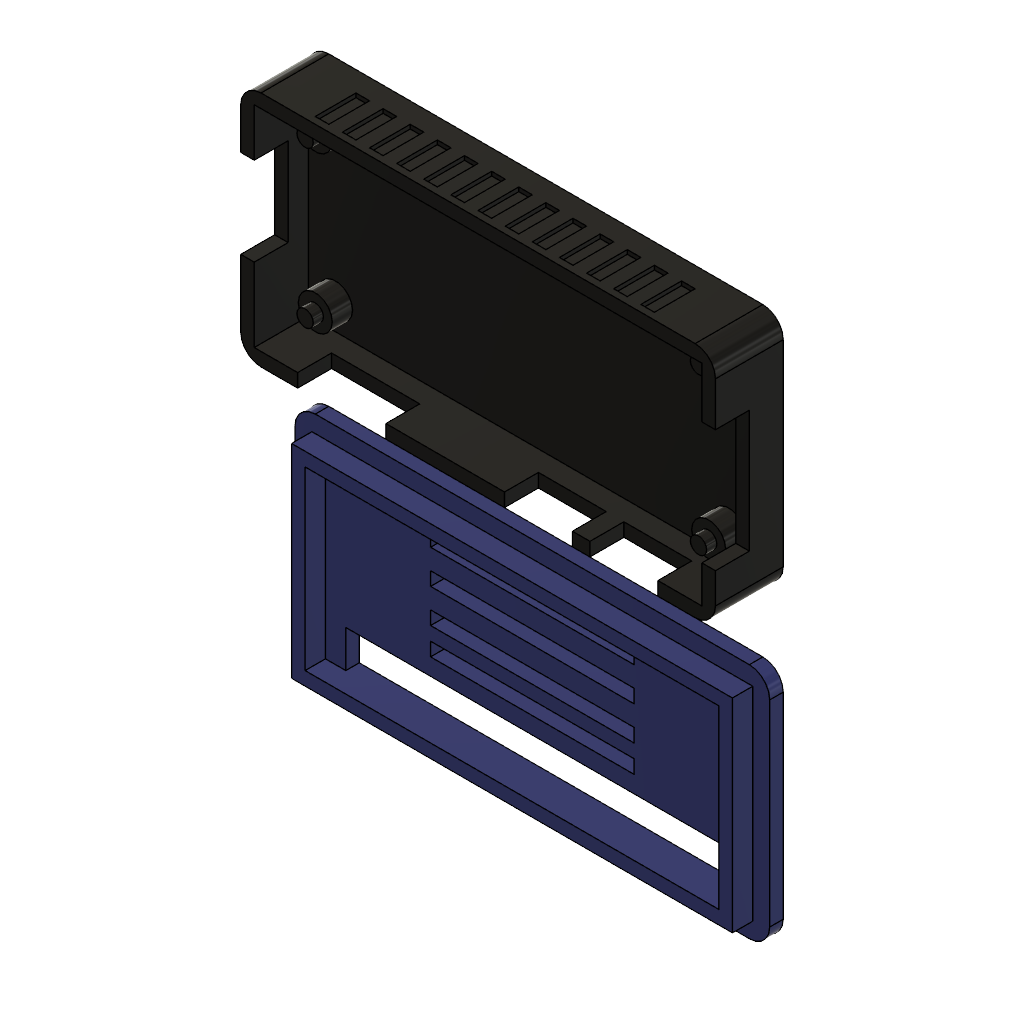
raspberry full assembly (Autodesk Fusion 360 archive; units mm, degrees)
design "raspberry"
part number: 2026-11-03-22-19-11-601
Autodesk Fusion 360 part; units mm, degrees
sketch "Sketch1" plane through (0, 0, 0) normal (0, 0, 1) x (1, 0, 0)
  line L0 (-35, -17.5) -> (35, -17.5)
  line L1 (35, -17.5) -> (35, 17.5)
  line L2 (35, 17.5) -> (-35, 17.5)
  line L3 (-35, 17.5) -> (-35, -17.5)
extrude "Extrude1" add sketch "Sketch1" along normal blind 10 makes body 1
ref_plane "WorkPlane1" through (0, 0, 2) normal (0, 0, 1) x (1, 0, 0)
sketch "Sketch2" plane through (0, 0, 2) normal (0, 0, 1) x (1, 0, 0)
  line L0 (-33, -15.5) -> (33, -15.5)
  line L1 (33, -15.5) -> (33, 15.5)
  line L2 (33, 15.5) -> (-33, 15.5)
  line L3 (-33, 15.5) -> (-33, -15.5)
extrude "Extrude2" cut sketch "Sketch2" along normal blind 8 bodies 1
sketch "Sketch3" plane through (0, 0, 2) normal (0, 0, 1) x (1, 0, 0)
  circle A0 centre (-29, -11.5) radius 2.5
  circle A1 centre (29, -11.5) radius 2.5
  circle A2 centre (-29, 11.5) radius 2.5
  circle A3 centre (29, 11.5) radius 2.5
extrude "Extrude3" add sketch "Sketch3" along normal blind 3 bodies 1
ref_plane "WorkPlane2" through (0, 0, 5) normal (0, 0, 1) x (1, 0, 0)
sketch "Sketch4" plane through (0, 0, 5) normal (0, 0, 1) x (1, 0, 0)
  circle A0 centre (-29, -11.5) radius 1.2
  circle A1 centre (29, -11.5) radius 1.2
  circle A2 centre (-29, 11.5) radius 1.2
  circle A3 centre (29, 11.5) radius 1.2
extrude "Extrude4" add sketch "Sketch4" along normal blind 1.5 bodies 1
ref_plane "WorkPlane3" through (0, 0, 10) normal (0, 0, 1) x (1, 0, 0)
sketch "Sketch5" plane through (0, 0, 10) normal (0, 0, 1) x (1, 0, 0)
  line L0 (-35, -17.5) -> (35, -17.5)
  line L1 (35, -17.5) -> (35, 17.5)
  line L2 (35, 17.5) -> (-35, 17.5)
  line L3 (-35, 17.5) -> (-35, -17.5)
extrude "Extrude5" add sketch "Sketch5" along normal blind 2 separate body makes body 2
sketch "Sketch6" plane through (0, 0, 10) normal (0, 0, 1) x (1, 0, 0)
  line L0 (-32.5, -15) -> (32.5, -15)
  line L1 (32.5, -15) -> (32.5, 15)
  line L2 (32.5, 15) -> (-32.5, 15)
  line L3 (-32.5, 15) -> (-32.5, -15)
extrude "Extrude6" add sketch "Sketch6" against normal blind 3 bodies 2
ref_plane "WorkPlane4" through (0, 0, 5) normal (0, 0, 1) x (1, 0, 0)
sketch "Sketch7" plane through (0, 0, 5) normal (0, 0, 1) x (1, 0, 0)
  line L0 (-26.6, -18) -> (-13.6, -18)
  line L1 (-13.6, -18) -> (-13.6, -15)
  line L2 (-13.6, -15) -> (-26.6, -15)
  line L3 (-26.6, -15) -> (-26.6, -18)
  line L4 (3.9, -18) -> (13.9, -18)
  line L5 (13.9, -18) -> (13.9, -15)
  line L6 (13.9, -15) -> (3.9, -15)
  line L7 (3.9, -15) -> (3.9, -18)
  line L8 (16.5, -18) -> (26.5, -18)
  line L9 (26.5, -18) -> (26.5, -15)
  line L10 (26.5, -15) -> (16.5, -15)
  line L11 (16.5, -15) -> (16.5, -18)
  line L12 (-35.5, -4.6) -> (-32, -4.6)
  line L13 (-32, -4.6) -> (-32, 8.4)
  line L14 (-32, 8.4) -> (-35.5, 8.4)
  line L15 (-35.5, 8.4) -> (-35.5, -4.6)
  line L16 (32, -10) -> (35.5, -10)
  line L17 (35.5, -10) -> (35.5, 8)
  line L18 (35.5, 8) -> (32, 8)
  line L19 (32, 8) -> (32, -10)
extrude "Extrude7" cut sketch "Sketch7" along normal blind 4.5 bodies 1
ref_plane "WorkPlane5" through (0, 0, 10) normal (0, 0, 1) x (1, 0, 0)
sketch "Sketch8" plane through (0, 0, 10) normal (0, 0, 1) x (1, 0, 0)
  line L0 (-30.5, -13) -> (30.5, -13)
  line L1 (30.5, -13) -> (30.5, 13)
  line L2 (30.5, 13) -> (-30.5, 13)
  line L3 (-30.5, 13) -> (-30.5, -13)
extrude "Extrude8" cut sketch "Sketch8" against normal blind 3 bodies 2
sketch "Sketch9" plane through (0, 0, 10) normal (0, 0, 1) x (1, 0, 0)
  line L0 (-15, -11) -> (15, -11)
  line L1 (15, -11) -> (15, -9)
  line L2 (15, -9) -> (-15, -9)
  line L3 (-15, -9) -> (-15, -11)
  line L4 (-15, -6) -> (15, -6)
  line L5 (15, -6) -> (15, -4)
  line L6 (15, -4) -> (-15, -4)
  line L7 (-15, -4) -> (-15, -6)
  line L8 (-15, -1) -> (15, -1)
  line L9 (15, -1) -> (15, 1)
  line L10 (15, 1) -> (-15, 1)
  line L11 (-15, 1) -> (-15, -1)
  line L12 (-15, 3) -> (15, 3)
  line L13 (15, 3) -> (15, 5)
  line L14 (15, 5) -> (-15, 5)
  line L15 (-15, 5) -> (-15, 3)
  line L16 (-27.5, 7.5) -> (27.5, 7.5)
  line L17 (27.5, 7.5) -> (27.5, 13)
  line L18 (27.5, 13) -> (-27.5, 13)
  line L19 (-27.5, 13) -> (-27.5, 7.5)
extrude "Extrude9" cut sketch "Sketch9" along normal blind 2 bodies 2
fillet "Fillet1" radius 3 4 edges at (-35, 17.5, 5) (35, 17.5, 5) (35, -17.5, 5) (-35, -17.5, 5) on bodies 1
fillet "Fillet2" radius 3 4 edges at (-35, 17.5, 11) (35, 17.5, 11) (35, -17.5, 11) (-35, -17.5, 11) on bodies 2
move_body "Move1" bodies 2 to x (1, 0, 0) y (0, -1, 0) z (0, 0, -1) at (0, -45, 12)
ref_plane "WorkPlane6" through (0, 0, 9) normal (0, 0, 1) x (1, 0, 0)
sketch "Sketch10" plane through (0, 0, 9) normal (0, 0, 1) x (1, 0, 0)
  line L0 (-26.6, -18) -> (-13.6, -18)
  line L1 (-13.6, -18) -> (-13.6, -15)
  line L2 (-13.6, -15) -> (-26.6, -15)
  line L3 (-26.6, -15) -> (-26.6, -18)
  line L4 (3.9, -18) -> (13.9, -18)
  line L5 (13.9, -18) -> (13.9, -15)
  line L6 (13.9, -15) -> (3.9, -15)
  line L7 (3.9, -15) -> (3.9, -18)
  line L8 (16.5, -18) -> (26.5, -18)
  line L9 (26.5, -18) -> (26.5, -15)
  line L10 (26.5, -15) -> (16.5, -15)
  line L11 (16.5, -15) -> (16.5, -18)
  line L12 (-35.5, -4.6) -> (-32, -4.6)
  line L13 (-32, -4.6) -> (-32, 8.4)
  line L14 (-32, 8.4) -> (-35.5, 8.4)
  line L15 (-35.5, 8.4) -> (-35.5, -4.6)
  line L16 (32, -10) -> (35.5, -10)
  line L17 (35.5, -10) -> (35.5, 8)
  line L18 (35.5, 8) -> (32, 8)
  line L19 (32, 8) -> (32, -10)
extrude "Extrude10" cut sketch "Sketch10" along normal blind 3 bodies 1
ref_plane "WorkPlane7" through (0, 0, 3) normal (0, 0, 1) x (1, 0, 0)
sketch "Sketch11" plane through (0, 0, 3) normal (0, 0, 1) x (1, 0, 0)
  line L0 (-25, 16.9) -> (-23, 16.9)
  line L1 (-23, 16.9) -> (-23, 18)
  line L2 (-23, 18) -> (-25, 18)
  line L3 (-25, 18) -> (-25, 16.9)
  line L4 (-21, 16.9) -> (-19, 16.9)
  line L5 (-19, 16.9) -> (-19, 18)
  line L6 (-19, 18) -> (-21, 18)
  line L7 (-21, 18) -> (-21, 16.9)
  line L8 (-17, 16.9) -> (-15, 16.9)
  line L9 (-15, 16.9) -> (-15, 18)
  line L10 (-15, 18) -> (-17, 18)
  line L11 (-17, 18) -> (-17, 16.9)
  line L12 (-13, 16.9) -> (-11, 16.9)
  line L13 (-11, 16.9) -> (-11, 18)
  line L14 (-11, 18) -> (-13, 18)
  line L15 (-13, 18) -> (-13, 16.9)
  line L16 (-9, 16.9) -> (-7, 16.9)
  line L17 (-7, 16.9) -> (-7, 18)
  line L18 (-7, 18) -> (-9, 18)
  line L19 (-9, 18) -> (-9, 16.9)
  line L20 (-5, 16.9) -> (-3, 16.9)
  line L21 (-3, 16.9) -> (-3, 18)
  line L22 (-3, 18) -> (-5, 18)
  line L23 (-5, 18) -> (-5, 16.9)
  line L24 (-1, 16.9) -> (1, 16.9)
  line L25 (1, 16.9) -> (1, 18)
  line L26 (1, 18) -> (-1, 18)
  line L27 (-1, 18) -> (-1, 16.9)
  line L28 (3, 16.9) -> (5, 16.9)
  line L29 (5, 16.9) -> (5, 18)
  line L30 (5, 18) -> (3, 18)
  line L31 (3, 18) -> (3, 16.9)
  line L32 (7, 16.9) -> (9, 16.9)
  line L33 (9, 16.9) -> (9, 18)
  line L34 (9, 18) -> (7, 18)
  line L35 (7, 18) -> (7, 16.9)
  line L36 (11, 16.9) -> (13, 16.9)
  line L37 (13, 16.9) -> (13, 18)
  line L38 (13, 18) -> (11, 18)
  line L39 (11, 18) -> (11, 16.9)
  line L40 (15, 16.9) -> (17, 16.9)
  line L41 (17, 16.9) -> (17, 18)
  line L42 (17, 18) -> (15, 18)
  line L43 (15, 18) -> (15, 16.9)
  line L44 (19, 16.9) -> (21, 16.9)
  line L45 (21, 16.9) -> (21, 18)
  line L46 (21, 18) -> (19, 18)
  line L47 (19, 18) -> (19, 16.9)
  line L48 (23, 16.9) -> (25, 16.9)
  line L49 (25, 16.9) -> (25, 18)
  line L50 (25, 18) -> (23, 18)
  line L51 (23, 18) -> (23, 16.9)
  line L52 (-31, -18) -> (-29, -18)
  line L53 (-29, -18) -> (-29, -16.9)
  line L54 (-29, -16.9) -> (-31, -16.9)
  line L55 (-31, -16.9) -> (-31, -18)
  line L56 (-10, -18) -> (-8, -18)
  line L57 (-8, -18) -> (-8, -16.9)
  line L58 (-8, -16.9) -> (-10, -16.9)
  line L59 (-10, -16.9) -> (-10, -18)
  line L60 (-6, -18) -> (-4, -18)
  line L61 (-4, -18) -> (-4, -16.9)
  line L62 (-4, -16.9) -> (-6, -16.9)
  line L63 (-6, -16.9) -> (-6, -18)
  line L64 (-2, -18) -> (0, -18)
  line L65 (0, -18) -> (0, -16.9)
  line L66 (0, -16.9) -> (-2, -16.9)
  line L67 (-2, -16.9) -> (-2, -18)
  line L68 (29, -18) -> (31, -18)
  line L69 (31, -18) -> (31, -16.9)
  line L70 (31, -16.9) -> (29, -16.9)
  line L71 (29, -16.9) -> (29, -18)
extrude "Extrude11" cut sketch "Sketch11" along normal blind 6 bodies 1
sketch "Sketch12" plane through (0, 0, 0) normal (0, 0, 1) x (1, 0, 0)
  line L0 (-32.5, -60) -> (32.5, -60)
  line L1 (32.5, -60) -> (32.5, -30)
  line L2 (32.5, -30) -> (-32.5, -30)
  line L3 (-32.5, -30) -> (-32.5, -60)
  line L4 (-31.9, -59.4) -> (31.9, -59.4)
  line L5 (31.9, -59.4) -> (31.9, -30.6)
  line L6 (31.9, -30.6) -> (-31.9, -30.6)
  line L7 (-31.9, -30.6) -> (-31.9, -59.4)
extrude "Extrude12" cut sketch "Sketch12" along normal blind 0.5 bodies 2
sketch "Sketch13" plane through (0, 0, 0) normal (0, 0, 1) x (1, 0, 0)
  circle A0 centre (-18, -49.8) radius 0.9
  circle A1 centre (-18, -47.4) radius 0.9
  circle A2 centre (-18, -45) radius 0.9
  circle A3 centre (-18, -42.6) radius 0.9
  circle A4 centre (-18, -40.2) radius 0.9
  circle A5 centre (-20.5, -49.8) radius 0.75
  circle A6 centre (-20.5, -47.4) radius 0.75
  circle A7 centre (-20.5, -45) radius 0.75
  circle A8 centre (-20.5, -42.6) radius 0.75
  circle A9 centre (-20.5, -40.2) radius 0.75
  circle A10 centre (-23, -49.8) radius 0.6
  circle A11 centre (-23, -47.4) radius 0.6
  circle A12 centre (-23, -45) radius 0.6
  circle A13 centre (-23, -42.6) radius 0.6
  circle A14 centre (-23, -40.2) radius 0.6
  circle A15 centre (-25.5, -49.8) radius 0.45
  circle A16 centre (-25.5, -47.4) radius 0.45
  circle A17 centre (-25.5, -45) radius 0.45
  circle A18 centre (-25.5, -42.6) radius 0.45
  circle A19 centre (-25.5, -40.2) radius 0.45
  circle A20 centre (-28, -49.8) radius 0.3
  circle A21 centre (-28, -47.4) radius 0.3
  circle A22 centre (-28, -45) radius 0.3
  circle A23 centre (-28, -42.6) radius 0.3
  circle A24 centre (-28, -40.2) radius 0.3
  circle A25 centre (18, -49.8) radius 0.9
  circle A26 centre (18, -47.4) radius 0.9
  circle A27 centre (18, -45) radius 0.9
  circle A28 centre (18, -42.6) radius 0.9
  circle A29 centre (18, -40.2) radius 0.9
  circle A30 centre (20.5, -49.8) radius 0.75
  circle A31 centre (20.5, -47.4) radius 0.75
  circle A32 centre (20.5, -45) radius 0.75
  circle A33 centre (20.5, -42.6) radius 0.75
  circle A34 centre (20.5, -40.2) radius 0.75
  circle A35 centre (23, -49.8) radius 0.6
  circle A36 centre (23, -47.4) radius 0.6
  circle A37 centre (23, -45) radius 0.6
  circle A38 centre (23, -42.6) radius 0.6
  circle A39 centre (23, -40.2) radius 0.6
  circle A40 centre (25.5, -49.8) radius 0.45
  circle A41 centre (25.5, -47.4) radius 0.45
  circle A42 centre (25.5, -45) radius 0.45
  circle A43 centre (25.5, -42.6) radius 0.45
  circle A44 centre (25.5, -40.2) radius 0.45
  circle A45 centre (28, -49.8) radius 0.3
  circle A46 centre (28, -47.4) radius 0.3
  circle A47 centre (28, -45) radius 0.3
  circle A48 centre (28, -42.6) radius 0.3
  circle A49 centre (28, -40.2) radius 0.3
extrude "Extrude13" cut sketch "Sketch13" along normal blind 0.4 bodies 2
named bodies: "Pi Zero 2W Case Base", "Pi Zero 2W Case Lid"
